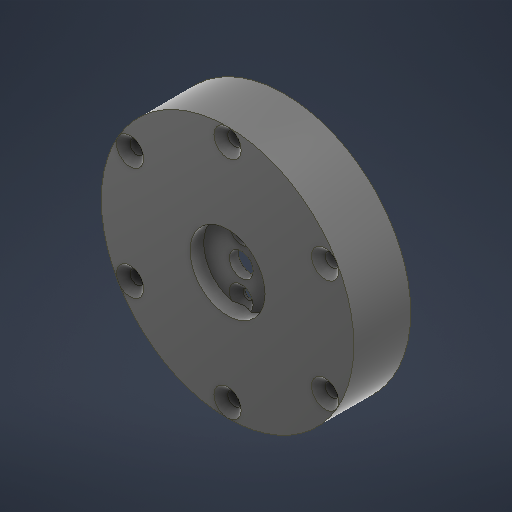
# Autodesk Inventor part: motor holder
Saved by Autodesk Inventor 2027.1 (Build 311270010, 270A)
## iProperties
Created: 2026-10-16
Part Number: motor holder
Material: Printed PLA Plastic
Document SubType Name: Modeling
Designer: youss
Density: 1.14 g/cm^3
Appearance: PLA (White)
Author: youss
Autodesk Inventor part; units mm, degrees
ref_plane "YZ Plane" through (0, 0, 0) normal (1, 0, 0) x (0, 1, 0)
ref_plane "XZ Plane" through (0, 0, 0) normal (0, 1, 0) x (-1, 0, 0)
ref_plane "XY Plane" through (0, 0, 0) normal (0, 0, 1) x (1, 0, 0)
sketch "Sketch1" plane through (0, 0, 0) normal (0, 0, 1) x (1, 0, 0)
  circle A0 centre (-1.5819, -0.0443) radius 30
  circle A1 centre (-1.5819, -0.0443) radius 37
  circle A2 centre (-1.5819, -33.0443) radius 2
  circle A3 centre (26.9969, -16.5443) radius 2
  circle A4 centre (26.9969, 16.4557) radius 2
  circle A5 centre (-1.5819, 32.9557) radius 2
  circle A6 centre (-30.1608, 16.4557) radius 2
  circle A7 centre (-30.1608, -16.5443) radius 2
  circle A8 centre (-1.5819, -8.5443) radius 1.5
  circle A9 centre (-1.5819, -0.0443) radius 12.5
  circle A10 centre (-10.0819, -0.0443) radius 2.75
  circle A11 centre (-1.5819, -8.5443) radius 1.5
  circle A12 centre (-1.5819, -0.0443) radius 3.5
  circle A13 centre (-1.5819, 8.4557) radius 1.5
  circle A14 centre (6.9181, -0.0443) radius 2.75
  line L0 (-1.5819, -0.0443) -> (-1.5819, -33.0443)
  dimension "d0" = 60
  dimension "d1" = 7
  dimension "d5" = 4
  dimension "d9" = 360
  dimension "d42" = 33
  constraints: 15 centre point, 2 concentric, 2 end point, 1 vertical, 15 other
  measures "d0" diameter of A0
  measures "d1" radial gap between concentric circles of A0 A1
  measures "d5" diameter of A2
  measures "d42" distance of A9.centre L0.end
extrude "Extrusion1" add sketch "Sketch1" along normal blind 6.66 contours A0 | A1 | A9 | A10 | A14
extrude "Extrusion2" add sketch "Sketch1" against normal blind 10 contours A1
chamfer "Chamfer2" distance 2 angle 45 6 edges at (-3.5819, 32.9557, 6.66) (24.9969, 16.4557, 6.66) (-32.1608, 16.4557, 6.66) (-32.1608, -16.5443, 6.66) (-3.5819, -33.0443, 6.66) (24.9969, -16.5443, 6.66)
sketch "Sketch8" plane through (-1.5819, -0.0443, 6.66) normal (0, 0, 1) x (1, 0, 0)
  circle A0 centre (0, 0) radius 3.5 projected
  circle A1 centre (0, 0) radius 11
  circle A2 centre (0, 0) radius 13
  point P0 (1.5819, 0.0443)
  dimension "d34" = 22
  dimension "d35" = 2
  constraints: 2 centre point, 1 coincident
  measures "d34" diameter of A1
  measures "d35" radial gap between concentric circles of A1 A2
extrude "Extrusion7" cut sketch "Sketch8" against normal blind 4 contours A1
chamfer "Chamfer4" distance 2 angle 45 2 edges at (-3.0819, 8.4557, 2.66) (-3.0819, -8.5443, 2.66)
body "Solid1"
